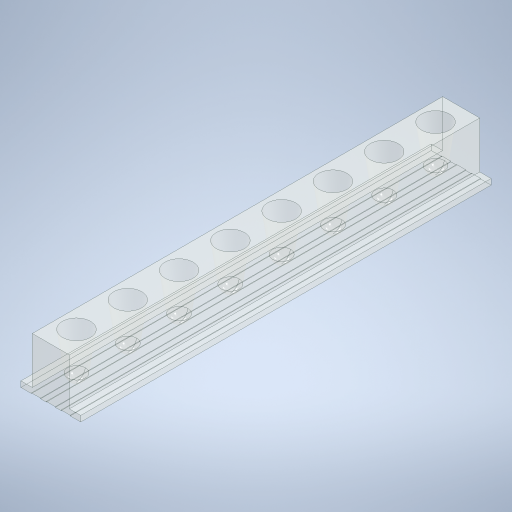
# Autodesk Inventor part: ThermalBlock v1_2_baru
Saved by Autodesk Inventor 2023.5 (Build 275446020, 446B)
## iProperties
Created: 2023-04-11
Part Number: ThermalBlock v1_2_baru
Material: Glass
Document SubType Name: Modeling
Designer: Achong
Density: 2.18 g/cm^3
Appearance: Clear
Author: Achong
Autodesk Inventor part; units mm, degrees
ref_plane "15.60" through (0, 15.5, 0) normal (0, 1, 0) x (-1, 0, 0)
sketch "Sketch1" plane through (0, 15.5, 0) normal (0, 1, 0) x (-1, 0, 0)
  circle A0 centre (0, 0) radius 2.75
  line L0 (0, 0) -> (0, -2.75)
  circle A1 centre (0, -9) radius 2.75
  circle A2 centre (0, -18) radius 2.75
  circle A3 centre (0, -27) radius 2.75
  circle A4 centre (0, -36) radius 2.75
  circle A5 centre (0, -45) radius 2.75
  circle A6 centre (0, -54) radius 2.75
  circle A7 centre (0, -63) radius 2.75
  circle A8 centre (0, 0) radius 4.05
  circle A9 centre (0, -9) radius 4.05
  circle A10 centre (0, -18) radius 4.05
  circle A11 centre (0, -27) radius 4.05
  circle A12 centre (0, -36) radius 4.05
  circle A13 centre (0, -45) radius 4.05
  circle A14 centre (0, -54) radius 4.05
  circle A15 centre (0, -63) radius 4.05
  arc A16 (4.05, -9) -> (4.05, 0) centre (-3.0797, -4.5) ccw
  arc A17 (3.9727, -8.2126) -> (3.9729, -0.7864) centre (-2.7676, -4.4993) ccw
  line L1 (0, 0) -> (4.05, 0)
  line L2 (0, 0) -> (-2.75, 0)
  arc A18 (-4.05, 0) -> (-4.05, -9) centre (3.0797, -4.5) ccw
  arc A19 (-3.9729, -0.7864) -> (-3.9727, -8.2126) centre (2.7676, -4.4993) ccw
  arc A20 (4.05, -18) -> (4.05, -9) centre (-3.0797, -13.5) ccw
  arc A21 (3.9727, -17.2126) -> (3.9729, -9.7864) centre (-2.7676, -13.4993) ccw
  arc A22 (4.05, -27) -> (4.05, -18) centre (-3.0797, -22.5) ccw
  arc A23 (3.9727, -26.2126) -> (3.9729, -18.7864) centre (-2.7676, -22.4993) ccw
  arc A24 (4.05, -36) -> (4.05, -27) centre (-3.0797, -31.5) ccw
  arc A25 (3.9727, -35.2126) -> (3.9729, -27.7864) centre (-2.7676, -31.4993) ccw
  arc A26 (4.05, -45) -> (4.05, -36) centre (-3.0797, -40.5) ccw
  arc A27 (3.9727, -44.2126) -> (3.9729, -36.7864) centre (-2.7676, -40.4993) ccw
  arc A28 (4.05, -54) -> (4.05, -45) centre (-3.0797, -49.5) ccw
  arc A29 (3.9727, -53.2126) -> (3.9729, -45.7864) centre (-2.7676, -49.4993) ccw
  arc A30 (4.05, -63) -> (4.05, -54) centre (-3.0797, -58.5) ccw
  arc A31 (3.9727, -62.2126) -> (3.9729, -54.7864) centre (-2.7676, -58.4993) ccw
  arc A32 (-3.9729, -9.7864) -> (-3.9727, -17.2126) centre (2.7676, -13.4993) ccw
  arc A33 (-4.05, -9) -> (-4.05, -18) centre (3.0797, -13.5) ccw
  arc A34 (-3.9729, -18.7864) -> (-3.9727, -26.2126) centre (2.7676, -22.4993) ccw
  arc A35 (-4.05, -18) -> (-4.05, -27) centre (3.0797, -22.5) ccw
  arc A36 (-3.9729, -27.7864) -> (-3.9727, -35.2126) centre (2.7676, -31.4993) ccw
  arc A37 (-4.05, -27) -> (-4.05, -36) centre (3.0797, -31.5) ccw
  arc A38 (-3.9729, -36.7864) -> (-3.9727, -44.2126) centre (2.7676, -40.4993) ccw
  arc A39 (-4.05, -36) -> (-4.05, -45) centre (3.0797, -40.5) ccw
  arc A40 (-3.9729, -45.7864) -> (-3.9727, -53.2126) centre (2.7676, -49.4993) ccw
  arc A41 (-4.05, -45) -> (-4.05, -54) centre (3.0797, -49.5) ccw
  arc A42 (-3.9729, -54.7864) -> (-3.9727, -62.2126) centre (2.7676, -58.4993) ccw
  arc A43 (-4.05, -54) -> (-4.05, -63) centre (3.0797, -58.5) ccw
  line L3 (4.05, 0) -> (-4.05, 0)
  line L4 (-4.05, 0) -> (-4.05, 4.75)
  line L5 (-2.05, 6.75) -> (2.05, 6.75)
  line L6 (4.05, 4.75) -> (4.05, 0)
  line L7 (4.05, -63) -> (-4.05, -63)
  line L8 (-4.05, -63) -> (-4.05, -67.75)
  line L9 (-2.05, -69.75) -> (2.05, -69.75)
  line L10 (4.05, -67.75) -> (4.05, -63)
  arc A44 (2.05, -69.75) -> (4.05, -67.75) centre (2.05, -67.75) ccw
  arc A45 (-4.05, -67.75) -> (-2.05, -69.75) centre (-2.05, -67.75) ccw
  arc A46 (4.05, 4.75) -> (2.05, 6.75) centre (2.05, 4.75) ccw
  arc A47 (-2.05, 6.75) -> (-4.05, 4.75) centre (-2.05, 4.75) ccw
  point P0 (0, -11.75)
  point P1 (0, -20.75)
  point P2 (0, -29.75)
  point P3 (0, -38.75)
  point P4 (0, -47.75)
  point P5 (0, -56.75)
  point P6 (0, -65.75)
  point P7 (-4.05, 6.75)
  point P8 (-4.05, -69.75)
  point P9 (4.05, -69.75)
  point P10 (3.9729, -54.7864)
  point P11 (3.9727, -62.2126)
  point P12 (3.9729, -45.7864)
  point P13 (3.9727, -53.2126)
  point P14 (3.9729, -36.7864)
  point P15 (3.9727, -44.2126)
  point P16 (3.9729, -27.7864)
  point P17 (3.9727, -35.2126)
  point P18 (3.9729, -18.7864)
  point P19 (3.9727, -26.2126)
  point P20 (3.9729, -9.7864)
  point P21 (3.9727, -17.2126)
  point P22 (-4.05, 0)
  point P23 (-4.05, 0)
  point P24 (-4.05, 0)
  point P25 (-3.9727, -62.2126)
  point P26 (-3.9729, -54.7864)
  point P27 (-4.05, -45)
  point P28 (-4.05, -45)
  point P29 (-4.05, -45)
  point P30 (-3.9727, -53.2126)
  point P31 (-3.9729, -45.7864)
  point P32 (-4.05, -36)
  point P33 (-4.05, -36)
  point P34 (-4.05, -36)
  point P35 (-3.9727, -44.2126)
  point P36 (-3.9729, -36.7864)
  point P37 (-4.05, -27)
  point P38 (-4.05, -27)
  point P39 (-4.05, -27)
  point P40 (-3.9727, -35.2126)
  point P41 (-3.9729, -27.7864)
  point P42 (-4.05, -18)
  point P43 (-4.05, -18)
  point P44 (-4.05, -18)
  point P45 (-3.9727, -26.2126)
  point P46 (-3.9729, -18.7864)
  point P47 (-4.05, -9)
  point P48 (-4.05, -9)
  point P49 (-4.05, -9)
  point P50 (-3.9727, -17.2126)
  point P51 (-3.9727, -8.2126)
  point P52 (-3.9729, -0.7864)
  dimension "d133" = 5.5
  dimension "d1" = 5.5
  dimension "d4" = 9
  dimension "d9" = 8.1
  dimension "d12" = 9
  dimension "d19" = 9
  dimension "d26" = 9
  dimension "d31" = 6.75
  dimension "d32" = 8.1
  dimension "d33" = 6.75
  dimension "d34" = 2
  constraints: 71 point on circle, 40 centre point, 22 end point, 11 vertical, 8 tangent, 7 vertical alignment, 6 point on line, 6 symmetric about line, 4 horizontal, 4 parallel, 3 equal radius, 2 coincident, 2 line through centre, 2 perpendicular, 142 other
  measures "d1" diameter of A0
  measures "d4" distance of L0.start point (0, -9)
  measures "d9" diameter of A8
  measures "d12" distance of L1.start A9.centre
  measures "d19" distance of A16.centre A20.centre
  measures "d26" distance of A19.centre A32.centre
  measures "d31" distance of L3.end point (-4.05, 6.75)
  measures "d32" distance of point (4.05, -69.75) point (-4.05, -69.75)
  measures "d33" distance of point (-4.05, -69.75) L7.end
  measures "d34" radius of A44
extrude "Extrusion1" add sketch "Sketch1" along normal blind 0.8 contours A16 A9 A17 A8 | A8 L4 A47 L5 A46 L6 | A8 A19 A9 A18 | A20 A10 A21 A9 | A9 A32 A10 A33 | A22 A11 A23 A10 | A10 A34 A11 A35 | A24 A12 A25 A11 | A11 A36 A12 A37 | A26 A13 A27 A12 | A12 A38 A13 A39 | A28 A14 A29 A13 | A13 A40 A14 A41 | A30 A15 A31 A14 | A14 A42 A15 A43 | L10 A44 L9 A45 L8 A15
extrude "Extrusion2" cut sketch "Sketch1" along normal blind 1.4 and the other way blind 1 contours L1 A8 L3 A0 | A0 L3 A8 L1 | A9 | A10 | A11 | A12 | A13 | A14 | L7 A7 A15 | A15 L7 A7 keep common part
ref_plane "1" through (0, 1, 0) normal (0, 1, 0) x (-1, 0, 0)
sketch "Sketch4" plane through (0, 15.5, 0) normal (0, -1, 0) x (1, 0, 0)
  circle A0 centre (0, 0) radius 2.75
  circle A1 centre (0, 0) radius 3
  line L0 (0, 0) -> (0, -2.75)
  circle A2 centre (0, 0) radius 2.75 projected
  circle A3 centre (0, -9) radius 3
  circle A4 centre (0, -9) radius 2.75
  circle A5 centre (0, -18) radius 3
  circle A6 centre (0, -18) radius 2.75
  circle A7 centre (0, -27) radius 3
  circle A8 centre (0, -27) radius 2.75
  circle A9 centre (0, -36) radius 3
  circle A10 centre (0, -36) radius 2.75
  circle A11 centre (0, -45) radius 3
  circle A12 centre (0, -45) radius 2.75
  circle A13 centre (0, -54) radius 3
  circle A14 centre (0, -54) radius 2.75
  circle A15 centre (0, -63) radius 3
  circle A16 centre (0, -63) radius 2.75
  dimension "d58" = 6
  dimension "d61" = 9
  dimension "d134" = 5.5
  constraints: 16 centre point, 9 coincident, 2 end point, 2 vertical, 1 vertical alignment, 29 other
  measures "d58" diameter of A1
  measures "d61" distance of L0.start A3.centre
  measures "d134" diameter of A16
extrude "Extrusion3" [suppressed]
sketch "Sketch5" plane through (0, 0, 0) normal (1, 0, 0) x (0, 1, 0)
  line L0 (15.5, -66) -> (14.5, -66) projected
  line L1 (14.5, -66) -> (0.9, -66)
  line L2 (0.9, -66) -> (0.9, -60)
  line L3 (0.9, -60) -> (14.5, -60)
  line L4 (14.5, -60) -> (14.5, -66)
  line L5 (14.5, -60) -> (14.5, -66) projected
  line L6 (14.5, -66) -> (0.1342, -64.0321)
  line L7 (14.5, -66) -> (29, -66) construction
  line L8 (14.5, -60) -> (0.1342, -61.9679)
  line L9 (14.5, -60) -> (29, -60) construction
  line L10 (14.5, -65.75) -> (14.5, -60.25) projected
  line L11 (14.5, -60.2554) -> (0.1482, -62.3235)
  line L12 (14.5, -60.2554) -> (29, -60.2554) construction
  line L13 (14.5, -65.7446) -> (0.1482, -63.6765)
  line L14 (14.5, -65.7446) -> (29, -65.7446) construction
  line L15 (0.1342, -64.0321) -> (0.1482, -63.6765)
  line L16 (0.1482, -62.3235) -> (0.1342, -61.9679)
  line L17 (14.5, -66) -> (14.5, -65.7446)
  line L18 (14.5, -60) -> (14.5, -60.2554)
  line L19 (14.5, -60) -> (14.5, -66)
  line L20 (2.4999, -63) -> (14.5, -63)
  line L21 (16.9, -67.05) -> (16.9, -58.95) projected
  ellipse E0 centre (4.296, -63) end of major axis (4.296, -64.5873) minor radius 1.7961
  ellipse E1 centre (4.296, -63) end of major axis (4.296, -64.2631) minor radius 1.4983
  line L22 (14.5, -51) -> (0.1342, -52.9679)
  line L23 (14.5, -51.2554) -> (0.1482, -53.3235)
  ellipse E2 centre (4.296, -54) end of major axis (4.296, -55.5873) minor radius 1.7961
  ellipse E3 centre (4.296, -54) end of major axis (4.296, -55.2631) minor radius 1.4983
  line L24 (2.4999, -54) -> (14.5, -54)
  line L25 (14.5, -56.7446) -> (0.1482, -54.6765)
  line L26 (14.5, -57) -> (0.1342, -55.0321)
  line L27 (0.1482, -53.3235) -> (0.1342, -52.9679)
  line L28 (0.1342, -55.0321) -> (0.1482, -54.6765)
  line L29 (14.5, -51) -> (14.5, -57)
  line L30 (14.5, -42) -> (0.1342, -43.9679)
  line L31 (14.5, -42.2554) -> (0.1482, -44.3235)
  ellipse E4 centre (4.296, -45) end of major axis (4.296, -46.5873) minor radius 1.7961
  ellipse E5 centre (4.296, -45) end of major axis (4.296, -46.2631) minor radius 1.4983
  line L32 (2.4999, -45) -> (14.5, -45)
  line L33 (14.5, -47.7446) -> (0.1482, -45.6765)
  line L34 (14.5, -48) -> (0.1342, -46.0321)
  line L35 (0.1482, -44.3235) -> (0.1342, -43.9679)
  line L36 (0.1342, -46.0321) -> (0.1482, -45.6765)
  line L37 (14.5, -42) -> (14.5, -48)
  line L38 (14.5, -33) -> (0.1342, -34.9679)
  line L39 (14.5, -33.2554) -> (0.1482, -35.3235)
  ellipse E6 centre (4.296, -36) end of major axis (4.296, -37.5873) minor radius 1.7961
  ellipse E7 centre (4.296, -36) end of major axis (4.296, -37.2631) minor radius 1.4983
  line L40 (2.4999, -36) -> (14.5, -36)
  line L41 (14.5, -38.7446) -> (0.1482, -36.6765)
  line L42 (14.5, -39) -> (0.1342, -37.0321)
  line L43 (0.1482, -35.3235) -> (0.1342, -34.9679)
  line L44 (0.1342, -37.0321) -> (0.1482, -36.6765)
  line L45 (14.5, -33) -> (14.5, -39)
  line L46 (14.5, -24) -> (0.1342, -25.9679)
  line L47 (14.5, -24.2554) -> (0.1482, -26.3235)
  ellipse E8 centre (4.296, -27) end of major axis (4.296, -28.5873) minor radius 1.7961
  ellipse E9 centre (4.296, -27) end of major axis (4.296, -28.2631) minor radius 1.4983
  line L48 (2.4999, -27) -> (14.5, -27)
  line L49 (14.5, -29.7446) -> (0.1482, -27.6765)
  line L50 (14.5, -30) -> (0.1342, -28.0321)
  line L51 (0.1482, -26.3235) -> (0.1342, -25.9679)
  line L52 (0.1342, -28.0321) -> (0.1482, -27.6765)
  line L53 (14.5, -24) -> (14.5, -30)
  line L54 (14.5, -15) -> (0.1342, -16.9679)
  line L55 (14.5, -15.2554) -> (0.1482, -17.3235)
  ellipse E10 centre (4.296, -18) end of major axis (4.296, -19.5873) minor radius 1.7961
  ellipse E11 centre (4.296, -18) end of major axis (4.296, -19.2631) minor radius 1.4983
  line L56 (2.4999, -18) -> (14.5, -18)
  line L57 (14.5, -20.7446) -> (0.1482, -18.6765)
  line L58 (14.5, -21) -> (0.1342, -19.0321)
  line L59 (0.1482, -17.3235) -> (0.1342, -16.9679)
  line L60 (0.1342, -19.0321) -> (0.1482, -18.6765)
  line L61 (14.5, -15) -> (14.5, -21)
  line L62 (14.5, -6) -> (0.1342, -7.9679)
  line L63 (14.5, -6.2554) -> (0.1482, -8.3235)
  ellipse E12 centre (4.296, -9) end of major axis (4.296, -10.5873) minor radius 1.7961
  ellipse E13 centre (4.296, -9) end of major axis (4.296, -10.2631) minor radius 1.4983
  line L64 (2.4999, -9) -> (14.5, -9)
  line L65 (14.5, -11.7446) -> (0.1482, -9.6765)
  line L66 (14.5, -12) -> (0.1342, -10.0321)
  line L67 (0.1482, -8.3235) -> (0.1342, -7.9679)
  line L68 (0.1342, -10.0321) -> (0.1482, -9.6765)
  line L69 (14.5, -6) -> (14.5, -12)
  line L70 (14.5, 3) -> (0.1342, 1.0321)
  line L71 (14.5, 2.7446) -> (0.1482, 0.6765)
  ellipse E14 centre (4.296, 0) end of major axis (4.296, -1.5873) minor radius 1.7961
  ellipse E15 centre (4.296, 0) end of major axis (4.296, -1.2631) minor radius 1.4983
  line L72 (2.4999, 0) -> (14.5, 0)
  line L73 (14.5, -2.7446) -> (0.1482, -0.6765)
  line L74 (14.5, -3) -> (0.1342, -1.0321)
  line L75 (0.1482, 0.6765) -> (0.1342, 1.0321)
  line L76 (0.1342, -1.0321) -> (0.1482, -0.6765)
  line L77 (14.5, 3) -> (14.5, -3)
  point P0 (0, 0)
  point P1 (3.8887, -64.2155)
  point P2 (2.7976, -63)
  point P3 (3.8962, -64.5475)
  point P4 (14.5, -56.75)
  point P5 (14.5, -51.25)
  point P6 (14.5, -47.75)
  point P7 (14.5, -42.25)
  point P8 (14.5, -38.75)
  point P9 (14.5, -33.25)
  point P10 (14.5, -29.75)
  point P11 (14.5, -24.25)
  point P12 (14.5, -20.75)
  point P13 (14.5, -15.25)
  point P14 (14.5, -11.75)
  point P15 (14.5, -6.25)
  point P16 (14.5, -2.75)
  point P17 (14.5, 2.75)
  point P18 (3.8887, -55.2155)
  point P19 (2.7976, -54)
  point P20 (3.8962, -55.5475)
  point P21 (3.8887, -46.2155)
  point P22 (2.7976, -45)
  point P23 (3.8962, -46.5475)
  point P24 (3.8887, -37.2155)
  point P25 (2.7976, -36)
  point P26 (3.8962, -37.5475)
  point P27 (3.8887, -28.2155)
  point P28 (2.7976, -27)
  point P29 (3.8962, -28.5475)
  point P30 (3.8887, -19.2155)
  point P31 (2.7976, -18)
  point P32 (3.8962, -19.5475)
  point P33 (3.8887, -10.2155)
  point P34 (2.7976, -9)
  point P35 (3.8962, -10.5475)
  point P36 (3.8887, -1.2155)
  point P37 (2.7976, 0)
  point P38 (2.4999, 0)
  point P39 (3.8962, -1.5475)
  point P40 (4.2011, -64.2605)
  point P41 (2.9854, -64.0854)
  point P42 (5.1485, -64.3971)
  point P43 (6.092, -63)
  point P44 (5.7943, -63)
  point P45 (4.1469, -64.5818)
  point P46 (2.9854, -1.0854)
  point P47 (2.9854, 1.0854)
  point P48 (3.8962, 1.5475)
  point P49 (6.092, 0)
  point P50 (5.1485, -1.3971)
  point P51 (5.1485, 1.3971)
  point P52 (4.1469, 1.5818)
  point P53 (4.1469, -1.5818)
  point P54 (5.7943, 0)
  point P55 (2.9854, -10.0854)
  point P56 (2.9854, -7.9146)
  point P57 (3.8962, -7.4525)
  point P58 (14.5, -9)
  point P59 (6.092, -9)
  point P60 (5.1485, -10.3971)
  point P61 (5.1485, -7.6029)
  point P62 (4.1469, -7.4182)
  point P63 (4.1469, -10.5818)
  point P64 (5.7943, -9)
  point P65 (2.9854, -19.0854)
  point P66 (2.9854, -16.9146)
  point P67 (3.8962, -16.4525)
  point P68 (6.092, -18)
  point P69 (5.1485, -19.3971)
  point P70 (5.1485, -16.6029)
  point P71 (4.1469, -16.4182)
  point P72 (4.1469, -19.5818)
  point P73 (5.7943, -18)
  point P74 (2.9854, -28.0854)
  point P75 (2.9854, -25.9146)
  point P76 (3.8962, -25.4525)
  point P77 (6.092, -27)
  point P78 (5.1485, -28.3971)
  point P79 (5.1485, -25.6029)
  point P80 (4.1469, -25.4182)
  point P81 (4.1469, -28.5818)
  point P82 (5.7943, -27)
  point P83 (2.9854, -37.0854)
  point P84 (2.9854, -34.9146)
  point P85 (3.8962, -34.4525)
  point P86 (6.092, -36)
  point P87 (5.1485, -37.3971)
  point P88 (5.1485, -34.6029)
  point P89 (4.1469, -34.4182)
  point P90 (4.1469, -37.5818)
  point P91 (5.7943, -36)
  point P92 (2.9854, -46.0854)
  point P93 (2.9854, -43.9146)
  point P94 (3.8962, -43.4525)
  point P95 (14.5, -45)
  point P96 (6.092, -45)
  point P97 (5.1485, -46.3971)
  point P98 (5.1485, -43.6029)
  point P99 (4.1469, -43.4182)
  point P100 (4.1469, -46.5818)
  point P101 (5.7943, -45)
  point P102 (2.9854, -55.0854)
  point P103 (2.9854, -52.9146)
  point P104 (3.8962, -52.4525)
  point P105 (6.092, -54)
  point P106 (5.1485, -55.3971)
  point P107 (5.1485, -52.6029)
  point P108 (4.1469, -52.4182)
  point P109 (4.1469, -55.5818)
  point P110 (5.7943, -54)
  point P111 (3.8962, -61.4525)
  point P112 (5.1485, -61.6029)
  dimension "d227" = 1.2631
  dimension "d228" = 1.5873
  dimension "d186" = 14.5
  dimension "d187" = 172.2
  dimension "d188" = 14.5
  dimension "d189" = 172.2
  dimension "d193" = 0.253
  dimension "d194" = 14.5
  dimension "d195" = 171.8
  dimension "d196" = 0.253
  dimension "d197" = 14.5
  dimension "d198" = 171.8
  dimension "d199" = 6
  dimension "d200" = 13.6
  dimension "d207" = 14.4001
  dimension "d214" = 9
  constraints: 148 end point, 18 point on line, 16 coincident, 15 vertical, 7 horizontal, 4 equal length, 3 collinear, 2 parallel, 1 midpoint, 1 perpendicular, 208 other
  measures "d186" distance of L0.end L6.end
  measures "d187" angle of L7 L6
  measures "d188" distance of L3.end L8.end
  measures "d189" angle of L8 L9
  measures "d193" distance from line of L8 L11.start
  measures "d194" distance of L11.start L11.end
  measures "d195" angle of L11 L12
  measures "d196" distance from line of L6 L13.start
  measures "d197" distance of L13.start L13.end
  measures "d198" angle of L14 L13
  measures "d199" distance of L1.end L2.end
  measures "d200" distance of L0.end L1.end
  measures "d207" distance from line of point (2.5, -63) L21
  measures "d214" distance of L3.end L22.start
revolve "Revolution28" add sketch "Sketch5" angle 360 about axis through (0, 2.4999, 0) along (0, 1, 0) contours L77 L71 E14 L70 | E14 L71 E15 L70 | L77 L72 E14 L71 | E14 L72 E15 L71 | L71 E15 L72 E14 | E15 L72 L71 | L71 E15
ref_plane "Work Plane4" through (0, 1.3, 0) normal (0, 1, 0) x (1, 0, 0)
sketch "Sketch11" plane through (0, 1.3, 0) normal (0, 1, 0) x (1, 0, 0)
  line L0 (-3.25, -4.5) -> (3.25, -4.5)
  line L1 (3.25, -4.5) -> (3.25, 67.5)
  line L2 (3.25, 67.5) -> (-3.25, 67.5)
  line L3 (-3.25, 67.5) -> (-3.25, -4.5)
  line L4 (0, -1.5475) -> (0, 0) projected
  dimension "d270" = 72
  dimension "d276" = 4.5
  dimension "d302" = 6.5
  dimension "d303" = 3.25
  constraints: 8 end point, 2 parallel, 1 horizontal, 1 perpendicular
  measures "d270" distance of L0.end L1.end
  measures "d276" distance from line of L4.end L0
  measures "d302" distance of L0.start L0.end
  measures "d303" distance between parallel lines of L4 L1
extrude "Extrusion6" add sketch "Sketch11" along normal blind 9.2
revolve "Revolution29" cut sketch "Sketch5" angle 360 about axis through (0, 2.4999, -63) along (0, 1, 0) contours L6 E0 L13 L4 | L6 E0 L13 E1 | L13 E0 L20 L4 | L13 E1 L20 E0 | E0 L20 E1 L13 | E1 L13 | L13 E1 L20
revolve "Revolution30" cut sketch "Sketch5" angle 360 about axis through (0, 2.4999, -54) along (0, 1, 0) contours L29 L25 E2 L24 | E2 L25 E3 L24 | L29 L26 E2 L25 | L24 E3 L25 E2 | E3 L25 L24 | E2 L26 L25 E3 | E3 L25
revolve "Revolution31" cut sketch "Sketch5" angle 360 about axis through (0, 2.4999, -45) along (0, 1, 0) contours L37 L33 E4 L32 | E4 L33 E5 L32 | L37 L34 E4 L33 | L32 E5 L33 E4 | E5 L33 L32 | E4 L34 L33 E5 | E5 L33
revolve "Revolution32" cut sketch "Sketch5" angle 360 about axis through (0, 2.4999, -36) along (0, 1, 0) contours L45 L41 E6 L40 | E6 L41 E7 L40 | L45 L42 E6 L41 | L40 E7 L41 E6 | E7 L41 L40 | E6 L42 L41 E7 | E7 L41
revolve "Revolution33" cut sketch "Sketch5" angle 360 about axis through (0, 2.4999, -27) along (0, 1, 0) contours L53 L49 E8 L48 | E8 L49 E9 L48 | L53 L50 E8 L49 | L48 E9 L49 E8 | E9 L49 L48 | E8 L50 L49 E9 | E9 L49
revolve "Revolution34" cut sketch "Sketch5" angle 360 about axis through (0, 2.4999, -18) along (0, 1, 0) contours L61 L57 E10 L56 | E10 L57 E11 L56 | L61 L58 E10 L57 | L56 E11 L57 E10 | E11 L57 L56 | E10 L58 L57 E11 | E11 L57
revolve "Revolution35" cut sketch "Sketch5" angle 360 about axis through (0, 2.4999, -9) along (0, 1, 0) contours L69 L65 E12 L64 | E12 L65 E13 L64 | L69 L66 E12 L65 | L64 E13 L65 E12 | E13 L65 L64 | E12 L66 L65 E13 | E13 L65
revolve "Revolution36" cut sketch "Sketch5" angle 360 about axis through (0, 2.4999, 0) along (0, 1, 0) contours L77 L73 E14 L72 | E14 L73 E15 L72 | L77 L74 E14 L73 | L72 E15 L73 E14 | E15 L73 L72 | E14 L74 L73 E15 | E15 L73
sketch "Sketch12" plane through (3.25, 1.3, 4.5) normal (1, 0, 0) x (0, 0, -1)
  circle A0 centre (5.3898, 2.568) radius 1
  point P0 (4.5, -1.3)
  dimension "d272" = 2
  constraints: 1 centre point
  measures "d272" diameter of A0
extrude "Extrusion7" [suppressed]
sketch "Sketch14" plane through (0, 1.3, 0) normal (0, 1, 0) x (1, 0, 0)
  line L0 (11.7, -5.5) -> (-4.3, -5.5)
  line L1 (-4.3, -5.5) -> (-4.3, 68.7)
  line L2 (-4.3, 68.7) -> (11.7, 68.7)
  line L3 (11.7, 68.7) -> (11.7, -5.5)
  line L4 (-3.25, -4.5) -> (3.25, -4.5) projected
  line L5 (-3.25, 67.5) -> (-3.25, -4.5) projected
  line L6 (3.25, -4.5) -> (3.25, 67.5) projected
  point P0 (0, 0)
  dimension "d280" = 74.2
  dimension "d281" = 16
  dimension "d282" = 1
  dimension "d283" = 1.05
  dimension "d284" = 8.45
  constraints: 8 end point, 2 parallel, 1 horizontal, 1 perpendicular
  measures "d280" distance of L2.end L0.start
  measures "d281" distance of L1.end L2.end
  measures "d282" distance between parallel lines of L4 L0
  measures "d283" distance between parallel lines of L1 L5
  measures "d284" distance between parallel lines of L6 L3
extrude "Extrusion8" [suppressed]
sketch "Sketch15" plane through (3.25, 10.5, 4.5) normal (1, 0, 0) x (0, 0, -1)
  circle A0 centre (67.5, -9) radius 1
  line L0 (0, 0) -> (72, 0) projected
  line L1 (72, -9.2) -> (72, 0) projected
  circle A1 centre (58.5, -9) radius 1
  circle A2 centre (49.5, -9) radius 1
  circle A3 centre (40.5, -9) radius 1
  circle A4 centre (31.5, -9) radius 1
  circle A5 centre (22.5, -9) radius 1
  circle A6 centre (13.5, -9) radius 1
  circle A7 centre (4.5, -9) radius 1
  point P0 (4.5, -10.5)
  dimension "d287" = 2
  dimension "d288" = 8
  dimension "d289" = 4.5
  dimension "d292" = 9
  constraints: 8 centre point, 1 horizontal, 14 other
  measures "d287" diameter of A0
  measures "d288" distance edge to line of A0 L0
  measures "d289" distance from line of L1 A0.centre
  measures "d292" distance of A0.centre A1.centre
extrude "Extrusion9" [suppressed]
sketch "Sketch16" plane through (3.25, 10.5, 4.5) normal (1, 0, 0) x (0, 0, -1)
  circle A0 centre (36, -10) radius 2
  point P0 (4.5, -10.5)
  dimension "d299" = 4
  constraints: 1 centre point
  measures "d299" diameter of A0
extrude "Extrusion10" [suppressed]
sketch "Sketch17" plane through (0, 1.3, 0) normal (0, -1, 0) x (1, 0, 0)
  circle A0 centre (0, -36) radius 2.4521 projected
  circle A1 centre (0, -27) radius 2.4521 projected
  line L0 (-4.25, -68.5) -> (4.25, -68.5)
  line L1 (4.25, -68.5) -> (4.25, 5.5)
  line L2 (4.25, 5.5) -> (-4.25, 5.5)
  line L3 (-4.25, 5.5) -> (-4.25, -68.5)
  line L4 (-4.25, -68.5) -> (4.25, 5.5) construction
  line L5 (4.25, -68.5) -> (-4.25, 5.5) construction
  line L6 (-3.25, 4.5) -> (3.25, 4.5) projected
  line L7 (-3.25, -67.5) -> (-3.25, 4.5) projected
  point P0 (0, 0)
  point P1 (0, -31.5)
  dimension "d305" = 8.5
  dimension "d306" = 74
  dimension "d307" = 1
  dimension "d308" = 1
  constraints: 10 end point, 2 midpoint, 1 horizontal, 1 parallel, 1 vertical, 3 other
  measures "d305" distance of L2.end L1.end
  measures "d306" distance of L1.end L1.start
  measures "d307" distance between parallel lines of L6 L2
  measures "d308" distance between parallel lines of L7 L3
extrude "Extrusion11" [suppressed]
sketch "Sketch18" plane through (-3.25, 1.3, 4.5) normal (0, 0, 1) x (1, 0, 0)
  line L0 (-2, 0) -> (-2, 1)
  line L1 (-2, 1) -> (8.5, 1)
  line L2 (8.5, 1) -> (8.5, -1)
  line L3 (0, 0) -> (6.5, 0) projected
  line L4 (8.5, -1) -> (-2, 1) construction
  line L5 (-2, -1) -> (8.5, 1) construction
  line L6 (0, 0) -> (0, 9.2) projected
  line L7 (-2, 0) -> (8.5, 0)
  point P0 (3.25, -1.3)
  point P1 (3.25, 0)
  dimension "d311" = 2
  dimension "d312" = 1
  constraints: 12 end point, 4 midpoint, 1 parallel
  measures "d311" distance between parallel lines of L0 L6
  measures "d312" distance between parallel lines of L3 L1
extrude "Extrusion12" add sketch "Sketch18" against normal blind 72
sketch "Sketch19" plane through (-3.25, 10.5, 4.5) normal (0, 0, 1) x (1, 0, 0)
  line L0 (0, 0) -> (6.5, 0) projected
  line L1 (3.25, 0) -> (3.25, -9.2)
  line L2 (-2, -9.2) -> (8.5, -9.2) projected
  line L3 (4.05, -9.3) -> (2.45, -9.3)
  line L4 (2.45, -9.3) -> (2.45, -9.1)
  line L5 (2.45, -9.1) -> (4.05, -9.1)
  line L6 (4.05, -9.1) -> (4.05, -9.3)
  line L7 (4.05, -9.3) -> (2.45, -9.1) construction
  line L8 (2.45, -9.3) -> (4.05, -9.1) construction
  line L9 (1.45, -9.3) -> (-0.15, -9.3)
  line L10 (-0.15, -9.3) -> (-0.15, -9.1)
  line L11 (-0.15, -9.1) -> (1.45, -9.1)
  line L12 (1.45, -9.1) -> (1.45, -9.3)
  line L13 (1.45, -9.3) -> (-0.15, -9.1) construction
  line L14 (-0.15, -9.3) -> (1.45, -9.1) construction
  line L15 (6.65, -9.3) -> (5.05, -9.3)
  line L16 (5.05, -9.3) -> (5.05, -9.1)
  line L17 (5.05, -9.1) -> (6.65, -9.1)
  line L18 (6.65, -9.1) -> (6.65, -9.3)
  line L19 (6.65, -9.3) -> (5.05, -9.1) construction
  line L20 (5.05, -9.3) -> (6.65, -9.1) construction
  point P0 (3.25, -10.5)
  point P1 (0.65, -9.2)
  point P2 (2.45, -9.2)
  point P3 (1.45, -9.2)
  point P4 (5.85, -9.2)
  point P5 (5.05, -9.2)
  point P6 (4.05, -9.2)
  dimension "d316" = 1.6
  dimension "d317" = 0.2
  dimension "d318" = 1.6
  dimension "d319" = 1
  dimension "d320" = 1.6
  dimension "d321" = 0.2
  dimension "d322" = 1
  constraints: 38 end point, 12 midpoint, 6 parallel, 3 horizontal, 3 perpendicular, 2 point on line
  measures "d316" distance of L4.end L5.end
  measures "d317" distance of L3.end L4.end
  measures "d318" distance of L10.end L11.end
  measures "d319" distance of point (2.45, -9.2) point (1.45, -9.2)
  measures "d320" distance of L16.end L17.end
  measures "d321" distance of L16.start L16.end
  measures "d322" distance of point (4.05, -9.2) point (5.05, -9.2)
extrude "Extrusion13" cut sketch "Sketch19" against normal blind 89.5
equation "\"d186\" = d188"
equation "\"d194\" = d188"
equation "\"d197\" = d188"
body "Solid1"
